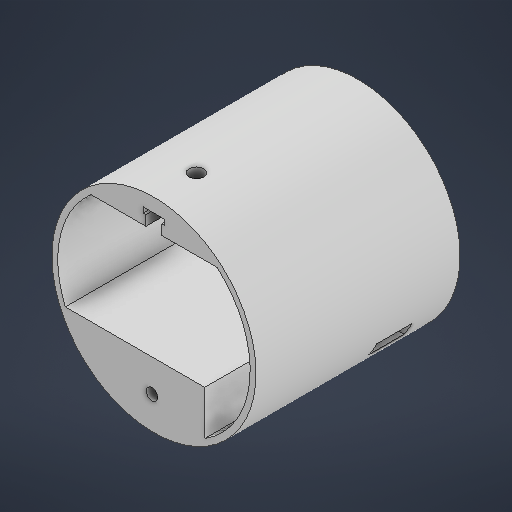
# Autodesk Inventor part: corps
Saved by Autodesk Inventor 2026.1 (Build 301233020, 233B)
## iProperties
Created: 2025-11-26
Part Number: corps
Material: Générique
Document SubType Name: Modeling
Designer: matpo
Density: 1 g/cm^3
Appearance: Par défaut
Author: matpo
Autodesk Inventor part; units mm, degrees
ref_plane "YZ Plane" through (0, 0, 0) normal (1, 0, 0) x (0, 1, 0)
ref_plane "XZ Plane" through (0, 0, 0) normal (0, 1, 0) x (-1, 0, 0)
ref_plane "XY Plane" through (0, 0, 0) normal (0, 0, 1) x (1, 0, 0)
sketch "Esquisse1" plane through (0, 0, 0) normal (0, 0, 1) x (1, 0, 0)
  arc A0 (3.519, -34.8226) -> (31.6228, -15) centre (0, 0) ccw projected
  line L0 (31.6228, -15) -> (13.2288, -15) projected
  arc A1 (13.2288, -15) -> (13.2288, 15) centre (0, 0) ccw projected
  line L1 (13.2288, 15) -> (31.6228, 15) projected
  arc A2 (31.6228, -15) -> (31.6228, 15) centre (11.6228, 0) ccw
  arc A3 (31.6228, 15) -> (3.7979, 34.7933) centre (0, 0) ccw projected
  circle A4 centre (0, 0) radius 35
  arc A5 (3.7979, 34.7933) -> (3.519, -34.8226) centre (0, 0) ccw projected
  arc A6 (4.6481, 3.7941) -> (0, 6) centre (0, 0) ccw projected
  line L2 (4.8734, 3.1618) -> (4.8734, -3.1618) projected
  arc A7 (0, -6) -> (4.6481, -3.7941) centre (0, 0) ccw projected
  circle A8 centre (21.5249, 18.9536) radius 1.9 projected
  circle A9 centre (21.5249, -18.9536) radius 1.9 projected
  circle A10 centre (14.7627, 0) radius 2 projected
  arc A11 (4.8734, 3.1618) -> (4.6481, 3.7941) centre (3.8734, 3.1618) ccw projected
  arc A12 (4.6481, -3.7941) -> (4.8734, -3.1618) centre (3.8734, -3.1618) ccw projected
  line L3 (0, -6) -> (0, 6) projected
  point P0 (3.7979, 34.7933)
  point P1 (3.519, -34.8226)
  point P2 (0, 0)
  point P3 (0, 0)
  point P4 (0, 0)
  point P5 (0, 0)
  point P6 (31.6228, -15)
  point P7 (0, 0)
  point P8 (0, 0)
  point P9 (0, 0)
  point P10 (0, 0)
  point P11 (0, 0)
  point P12 (0, 0)
  point P13 (0, 0)
  point P14 (0, 0)
  point P15 (0, 0)
  point P16 (0, 0)
  point P17 (0, 0)
  point P18 (0, 0)
  point P19 (0, 0)
  point P20 (0, 0)
  point P21 (0, 0)
  point P22 (0, 0)
  point P23 (0, 0)
  point P24 (0, 0)
  constraints: 2 centre point, 2 point on circle, 1 concentric, 1 other
extrude "Extrusion1" add sketch "Esquisse1" along normal blind 70 contours A4 A3 L1 A1 L0 A0 | L0 A1 L1 A4 | A11 L2 A12 A7 L3 A6 | A8 | A9 | A10
shell "Coque1" thickness 2 removed faces 1 at (-3.6713, -3.3568, 70)
sketch "Esquisse2" plane through (0, 0, 2) normal (0, 0, 1) x (1, 0, 0)
  point P0 (0, 0)
sketch "Esquisse3" plane through (0, 0, 2) normal (0, 0, 1) x (1, 0, 0)
  circle A0 centre (29.0925, 0) radius 2.4 projected
  arc A1 (-35, -53.7891) -> (-33.5, -55.2891) centre (-33.5, -53.7891) ccw projected
  line L0 (0, -55.2891) -> (-33.5, -55.2891) projected
  arc A2 (0, -55.2891) -> (0, 55.2891) centre (1.5734, 0) ccw projected
  line L1 (-33.5, 55.2891) -> (0, 55.2891) projected
  arc A3 (-33.5, 55.2891) -> (-35, 53.7891) centre (-33.5, 53.7891) ccw projected
  line L2 (-35, 52.7874) -> (-35, 53.7891) projected
  arc A4 (-35, 52.7874) -> (-33.5, 51.2874) centre (-33.5, 52.7874) ccw projected
  line L3 (0, 51.2874) -> (-33.5, 51.2874) projected
  arc A5 (42.7034, 30.679) -> (0, 51.2874) centre (1.5734, 0) ccw projected
  arc A6 (34.6877, 14.7) -> (42.7034, 30.679) centre (34.6877, 24.7) ccw projected
  line L4 (14, 14.7) -> (34.6877, 14.7) projected
  arc A7 (14, -14.7) -> (14, 14.7) centre (0, 0) ccw projected
  line L5 (34.6877, -14.7) -> (14, -14.7) projected
  arc A8 (42.7034, -30.679) -> (34.6877, -14.7) centre (34.6877, -24.7) ccw projected
  arc A9 (0, -51.2874) -> (42.7034, -30.679) centre (1.5734, 0) ccw projected
  line L6 (-33.5, -51.2874) -> (0, -51.2874) projected
  arc A10 (-33.5, -51.2874) -> (-35, -52.7874) centre (-33.5, -52.7874) ccw projected
  line L7 (-35, -53.7891) -> (-35, -52.7874) projected
  line L8 (-1, -3.8153) -> (-1, 3.8153) projected
  line L9 (9.6767, -25.678) -> (13.6386, -32.2334) projected
  arc A11 (9.6767, -25.678) -> (-1.3271, -18.9536) centre (-2.305, -32.9194) ccw projected
  arc A12 (-18.1552, -5.6027) -> (-1.3271, -18.9536) centre (0, 0) ccw projected
  arc A13 (-17.719, -3.8493) -> (-18.1552, -5.6027) centre (7.2859, -11) ccw projected
  arc A14 (-17.719, -3.8493) -> (-17.719, 3.8493) centre (-31.1794, 0) ccw projected
  arc A15 (-18.1552, 5.6027) -> (-17.719, 3.8493) centre (7.2859, 11) ccw projected
  arc A16 (-1.3271, 18.9536) -> (-18.1552, 5.6027) centre (0, 0) ccw projected
  arc A17 (-1.3271, 18.9536) -> (9.6767, 25.678) centre (-2.305, 32.9194) ccw projected
  line L10 (13.6386, 32.2334) -> (9.6767, 25.678) projected
  arc A18 (13.6386, -32.2334) -> (13.6386, 32.2334) centre (0, 0) ccw projected
  circle A19 centre (1.5734, 0) radius 18.7266 construction
  circle A20 centre (1.5734, 0) radius 27.519 construction
  arc A21 (10.3581, -5.4405) -> (10.3581, 5.4405) centre (14.7627, 0) ccw projected
  arc A22 (10.3581, 5.4405) -> (1.4625, 11.6082) centre (0, 0) ccw projected
  arc A23 (1.4625, 11.6082) -> (-2.7, 7.9373) centre (1, 7.9373) ccw projected
  line L11 (-2.7, 6.9282) -> (-2.7, 7.9373) projected
  arc A24 (-2.7, 6.9282) -> (-1, 3.8153) centre (1, 6.9282) ccw projected
  arc A25 (-1, -3.8153) -> (-2.7, -6.9282) centre (1, -6.9282) ccw projected
  line L12 (-2.7, -7.9373) -> (-2.7, -6.9282) projected
  arc A26 (-2.7, -7.9373) -> (1.4625, -11.6082) centre (1, -7.9373) ccw projected
  arc A27 (1.4625, -11.6082) -> (10.3581, -5.4405) centre (0, 0) ccw projected
  point P0 (0, 0)
  point P1 (21.5249, 18.9536)
  point P2 (21.5249, -18.9536)
  constraints: 3 point on circle, 2 centre point, 2 coincident, 2 horizontal alignment
hole "Perçage1" at (21.5249, 18.9536, 2) at (21.5249, -18.9536, 2) direction (0, 0, -1) diameter 2.7 end through all counterbore diameter 4.8 counterbore depth 2.4
sketch "Esquisse4" plane through (0, 0, 2) normal (0, 0, 1) x (1, 0, 0)
  circle A0 centre (21.5249, 18.9536) radius 1.9 projected
  circle A1 centre (21.5249, -18.9536) radius 1.9 projected
  arc A2 (3.7979, 34.7933) -> (3.519, -34.8226) centre (0, 0) ccw projected
  arc A3 (3.519, -34.8226) -> (31.6228, -15) centre (0, 0) ccw projected
  line L0 (31.6228, -15) -> (13.2288, -15) projected
  arc A4 (13.2288, -15) -> (13.2288, 15) centre (0, 0) ccw projected
  line L1 (13.2288, 15) -> (31.6228, 15) projected
  arc A5 (31.6228, 15) -> (3.7979, 34.7933) centre (0, 0) ccw projected
  arc A6 (4.6481, 3.7941) -> (0, 6) centre (0, 0) ccw projected
  arc A7 (4.8734, 3.1618) -> (4.6481, 3.7941) centre (3.8734, 3.1618) ccw projected
  line L2 (4.8734, 3.1618) -> (4.8734, -3.1618) projected
  arc A8 (4.6481, -3.7941) -> (4.8734, -3.1618) centre (3.8734, -3.1618) ccw projected
  arc A9 (0, -6) -> (4.6481, -3.7941) centre (0, 0) ccw projected
  line L3 (0, -6) -> (0, 6) projected
  circle A10 centre (14.7627, 0) radius 2 projected
  point P0 (0, 0)
extrude "Extrusion2" cut sketch "Esquisse4" against normal through all contours A7 L2 A8 A9 L3 A6
sketch "Esquisse5" plane through (0, 0, 2) normal (0, 0, 1) x (1, 0, 0)
  line L0 (0, -6) -> (0, 6) projected
  arc A0 (4.6481, 3.7941) -> (0, 6) centre (0, 0) ccw projected
  arc A1 (4.8734, 3.1618) -> (4.6481, 3.7941) centre (3.8734, 3.1618) ccw projected
  line L1 (4.8734, 3.1618) -> (4.8734, -3.1618) projected
  arc A2 (4.6481, -3.7941) -> (4.8734, -3.1618) centre (3.8734, -3.1618) ccw projected
  arc A3 (0, -6) -> (4.6481, -3.7941) centre (0, 0) ccw projected
  circle A4 centre (21.5249, -18.9536) radius 2.4 projected
  circle A5 centre (21.5249, 18.9536) radius 2.4 projected
  circle A6 centre (0, 0) radius 33 projected
  line L2 (-30.4052, -12.8267) -> (17.3956, -12.8267)
  line L3 (-21.6043, 24.945) -> (21.6043, 24.945)
  line L4 (17.3956, -12.8267) -> (17.3956, -28.0427)
  line L5 (17.3956, -12.8267) -> (30.4052, -12.8267) construction
  point P0 (0, 0)
  constraints: 8 end point, 6 point on circle, 3 horizontal, 1 point on line, 1 vertical
extrude "Extrusion3" add sketch "Esquisse5" along normal up to surface (68 mm away) contours L3 A6 | A6 L2 L4
sketch "Esquisse14" plane through (0, 0, 70) normal (0, 0, 1) x (1, 0, 0)
  circle A0 centre (-0.6882, -23.91) radius 2
  line L0 (-0.6882, -23.91) -> (-0.6882, -34.9932) construction
  circle A1 centre (0, 0) radius 35 construction
  line L1 (-0.6882, -23.91) -> (-0.6882, -12.8267) construction
  line L2 (-30.4052, -12.8267) -> (17.3956, -12.8267) construction
  point P0 (0, 0)
  point P1 (29.0231, -12.2437)
  point P2 (17.3956, -12.8267)
  dimension "d51" = 4
  constraints: 4 end point, 1 centre point, 1 collinear, 1 point on line, 1 vertical, 4 other
  measures "d51" diameter of A0
extrude "Extrusion10" cut sketch "Esquisse14" against normal blind 8
sketch "Esquisse15" plane through (-30.4052, -12.8267, 2) normal (0, 0, 1) x (1, 0, 0)
  circle A0 centre (45.1679, 12.8267) radius 2 projected
  point P0 (30.4052, 12.8267)
extrude "Extrusion11" cut sketch "Esquisse15" against normal through all
sketch "Esquisse16" plane through (-30.4052, -12.8267, 2) normal (0, 1, 0) x (1, 0, 0)
  line L0 (0, -68) -> (47.8008, -68) projected
  line L1 (0, -68) -> (0, 0) projected
  line L2 (0, 0) -> (47.8008, 0) projected
  line L3 (30.4052, 2) -> (35.0533, 2) projected
  line L4 (30.4052, 0) -> (30.4052, 2) projected
  line L5 (35.0533, 0) -> (30.4052, 0) projected
  line L6 (35.0533, 0) -> (35.0533, 2) projected
  line L7 (43.1679, 2) -> (47.1679, 2) projected
  line L8 (47.1679, 0) -> (43.1679, 0) projected
  line L9 (42.8566, -5) -> (52.8566, -5)
  line L10 (52.8566, -5) -> (52.8566, -12)
  line L11 (52.8566, -12) -> (42.8566, -12)
  line L12 (42.8566, -12) -> (42.8566, -11)
  line L13 (61.8566, -23) -> (52.8566, -23)
  line L14 (52.8566, -23) -> (52.8566, -12)
  line L15 (42.8566, -6) -> (-0.2255, -6)
  line L16 (-0.2255, -6) -> (-0.2255, -11)
  line L17 (-0.2255, -11) -> (42.8566, -11)
  line L18 (42.8566, -6) -> (42.8566, -5)
  line L19 (47.8008, 0) -> (47.8008, -68) projected
  line L20 (52.0095, -68) -> (52.0095, 0) projected
  line L21 (47.8008, 0) -> (52.0095, 0) projected
  line L22 (47.8008, 0) -> (47.8008, -68) projected
  line L23 (52.0095, -68) -> (47.8008, -68) projected
  line L24 (47.8008, 0) -> (47.8008, -68) construction
  line L25 (47.8008, -68) -> (70.585, -68) construction
  line L26 (-4.5948, -68) -> (65.4052, -68) construction
  line L27 (-4.5948, 2) -> (65.4052, 2) construction
  line L28 (61.8566, -23) -> (61.8566, -11)
  line L29 (61.8566, -11) -> (52.8566, -11)
  line L30 (7.8566, -11) -> (7.8566, -6)
  point P0 (30.4052, 2)
  point P1 (0, -21)
  point P2 (57.3566, -23)
  point P3 (52.8566, -8.5)
  point P4 (47.8008, -12)
  point P5 (0, -6)
  point P6 (0, -11)
  point P7 (47.8008, -12)
  point P8 (47.8008, -5)
  dimension "d56" = 10
  dimension "d57" = 7
  dimension "d58" = 9
  dimension "d61" = 5
  dimension "d62" = 5
  dimension "d66" = 12
  dimension "d67" = 11
  dimension "d68" = 35
  constraints: 28 end point, 5 point on line, 4 horizontal, 4 parallel, 4 perpendicular, 2 midpoint, 2 vertical, 1 collinear, 1 vertical alignment
  measures "d56" distance of L10.end L11.end
  measures "d57" distance of L9.end L10.end
  measures "d58" distance of L13.start L13.end
  measures "d61" distance between parallel lines of L2 L9
  measures "d62" distance of L15.end L16.end
  measures "d66" distance of L13.start L28.end
  measures "d67" distance of L13.end L10.end
  measures "d68" distance from line of L11.end L30
extrude "Extrusion12" cut sketch "Esquisse16" against normal blind 7 contours L19 L9 L20 L11 | L11 L12 L17 L30 L15 L18 L9 L19 | L20 L9 L10 L11 | L10 L29 L28 L13 L14
sketch "Esquisse17" plane through (0, 0, 70) normal (0, 0, 1) x (1, 0, 0)
  circle A0 centre (-0.6882, -23.91) radius 2 projected
  arc A1 (-21.6043, 24.945) -> (-30.4052, -12.8267) centre (0, 0) ccw projected
  line L0 (21.6043, 24.945) -> (-21.6043, 24.945) projected
  arc A2 (17.3956, -28.0427) -> (21.6043, 24.945) centre (0, 0) ccw projected
  line L1 (17.3956, -12.8267) -> (17.3956, -28.0427) projected
  line L2 (-30.4052, -12.8267) -> (17.3956, -12.8267) projected
  circle A3 centre (0, 0) radius 35 projected
  line L3 (0, 35) -> (0, 24.945) construction
  line L4 (-3.7, 30.245) -> (3.7, 30.245)
  line L5 (3.7, 30.245) -> (3.7, 28.445)
  line L6 (3.7, 28.445) -> (-3.7, 28.445)
  line L7 (-3.7, 28.445) -> (-3.7, 30.245)
  line L8 (21.6043, 24.945) -> (-21.6043, 24.945) projected
  line L9 (-2.75, 28.445) -> (2.75, 28.445)
  line L10 (2.75, 28.445) -> (2.75, 24.945)
  line L11 (2.75, 24.945) -> (-2.75, 24.945)
  line L12 (-2.75, 24.945) -> (-2.75, 28.445)
  point P0 (0, 0)
  point P1 (0, 30.245)
  point P2 (0, 28.445)
  dimension "d69" = 7.4
  dimension "d70" = 5.5
  dimension "d71" = 3.5
  dimension "d72" = 1.8
  constraints: 18 end point, 4 parallel, 4 point on line, 3 midpoint, 2 horizontal, 2 perpendicular, 1 vertical, 1 vertical alignment, 1 other
  measures "d69" distance between parallel lines of L5 L7
  measures "d70" distance between parallel lines of L10 L12
  measures "d71" distance of L9.end L10.end
  measures "d72" distance of L4.end L5.end
extrude "Extrusion13" cut sketch "Esquisse17" against normal blind 20 contours L12 L6 L10 L0 | L6 L7 L4 L5
sketch "Esquisse18" plane through (-3.7, 30.245, 70) normal (0, -1, 0) x (1, 0, 0)
  line L0 (0, 0) -> (7.4, 0) projected
  line L1 (0, 0) -> (0, -20) projected
  line L2 (0, -20) -> (7.4, -20) projected
  line L3 (7.4, 0) -> (7.4, -20) projected
  line L4 (3.7, -20) -> (3.7, 0) construction
  circle A0 centre (3.7, -14.5) radius 2.5
  point P0 (3.7, -70)
  dimension "d75" = 5
  dimension "d76" = 5.5
  constraints: 2 end point, 2 midpoint, 1 centre point, 1 point on line
  measures "d75" diameter of A0
  measures "d76" distance from line of L2 A0.centre
extrude "Extrusion14" cut sketch "Esquisse18" against normal through all contours A0
